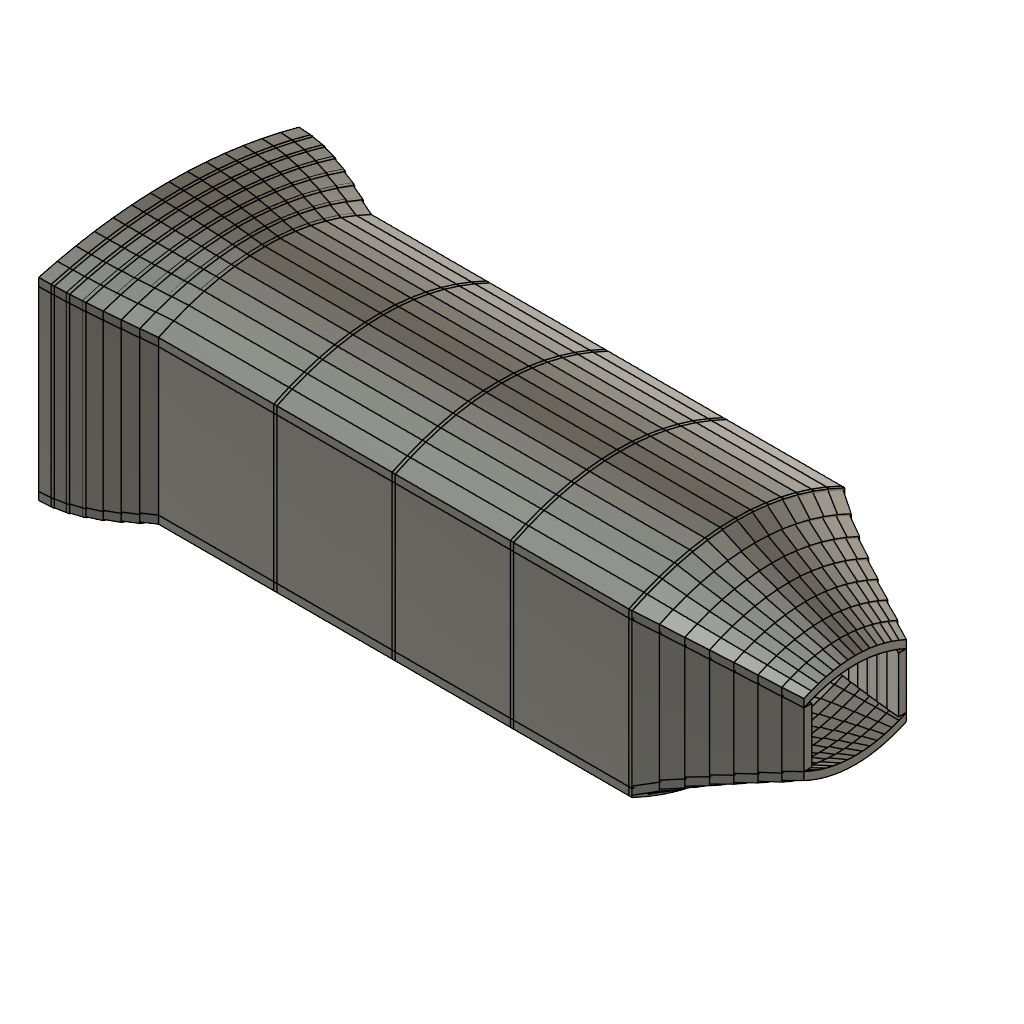
v22-casing (Autodesk Fusion 360 design; units mm, degrees)
part number: 2026-10-21-10-23-17-566
Autodesk Fusion 360 part; units mm, degrees
(part 1 of 5)
ref_plane "WorkPlane1" through (-24, 0, 0) normal (1, 0, 0) x (0, 1, 0)
sketch "roof_pa00" plane through (-24, 0, 0) normal (1, 0, 0) x (0, 0, -1)
  line L0 (-24.5, -33) -> (-25.6939, -28.2857)
  line L1 (-25.6939, -28.2857) -> (-26.7041, -23.5714)
  line L2 (-26.7041, -23.5714) -> (-27.5306, -18.8571)
  line L3 (-27.5306, -18.8571) -> (-28.1735, -14.1429)
  line L4 (-28.1735, -14.1429) -> (-28.6327, -9.4286)
  line L5 (-28.6327, -9.4286) -> (-28.9082, -4.7143)
  line L6 (-28.9082, -4.7143) -> (-29, 0)
  line L7 (-29, 0) -> (-28.9082, 4.7143)
  line L8 (-28.9082, 4.7143) -> (-28.6327, 9.4286)
  line L9 (-28.6327, 9.4286) -> (-28.1735, 14.1429)
  line L10 (-28.1735, 14.1429) -> (-27.5306, 18.8571)
  line L11 (-27.5306, 18.8571) -> (-26.7041, 23.5714)
  line L12 (-26.7041, 23.5714) -> (-25.6939, 28.2857)
  line L13 (-25.6939, 28.2857) -> (-24.5, 33)
  line L14 (-24.5, 33) -> (-22.5, 33)
  line L15 (-22.5, 33) -> (-23.6939, 28.2857)
  line L16 (-23.6939, 28.2857) -> (-24.7041, 23.5714)
  line L17 (-24.7041, 23.5714) -> (-25.5306, 18.8571)
  line L18 (-25.5306, 18.8571) -> (-26.1735, 14.1429)
  line L19 (-26.1735, 14.1429) -> (-26.6327, 9.4286)
  line L20 (-26.6327, 9.4286) -> (-26.9082, 4.7143)
  line L21 (-26.9082, 4.7143) -> (-27, 0)
  line L22 (-27, 0) -> (-26.9082, -4.7143)
  line L23 (-26.9082, -4.7143) -> (-26.6327, -9.4286)
  line L24 (-26.6327, -9.4286) -> (-26.1735, -14.1429)
  line L25 (-26.1735, -14.1429) -> (-25.5306, -18.8571)
  line L26 (-25.5306, -18.8571) -> (-24.7041, -23.5714)
  line L27 (-24.7041, -23.5714) -> (-23.6939, -28.2857)
  line L28 (-23.6939, -28.2857) -> (-22.5, -33)
  line L29 (-22.5, -33) -> (-24.5, -33)
ref_plane "WorkPlane2" through (-20.1714, 0, 0) normal (1, 0, 0) x (0, 1, 0)
sketch "roof_pb00" plane through (-20.1714, 0, 0) normal (1, 0, 0) x (0, 0, -1)
  line L0 (-24.3997, -32.8496) -> (-25.6069, -28.1568)
  line L1 (-25.6069, -28.1568) -> (-26.6284, -23.464)
  line L2 (-26.6284, -23.464) -> (-27.4641, -18.7712)
  line L3 (-27.4641, -18.7712) -> (-28.1141, -14.0784)
  line L4 (-28.1141, -14.0784) -> (-28.5784, -9.3856)
  line L5 (-28.5784, -9.3856) -> (-28.857, -4.6928)
  line L6 (-28.857, -4.6928) -> (-28.9499, 0)
  line L7 (-28.9499, 0) -> (-28.857, 4.6928)
  line L8 (-28.857, 4.6928) -> (-28.5784, 9.3856)
  line L9 (-28.5784, 9.3856) -> (-28.1141, 14.0784)
  line L10 (-28.1141, 14.0784) -> (-27.4641, 18.7712)
  line L11 (-27.4641, 18.7712) -> (-26.6284, 23.464)
  line L12 (-26.6284, 23.464) -> (-25.6069, 28.1568)
  line L13 (-25.6069, 28.1568) -> (-24.3997, 32.8496)
  line L14 (-24.3997, 32.8496) -> (-22.3997, 32.8496)
  line L15 (-22.3997, 32.8496) -> (-23.6069, 28.1568)
  line L16 (-23.6069, 28.1568) -> (-24.6284, 23.464)
  line L17 (-24.6284, 23.464) -> (-25.4641, 18.7712)
  line L18 (-25.4641, 18.7712) -> (-26.1141, 14.0784)
  line L19 (-26.1141, 14.0784) -> (-26.5784, 9.3856)
  line L20 (-26.5784, 9.3856) -> (-26.857, 4.6928)
  line L21 (-26.857, 4.6928) -> (-26.9499, 0)
  line L22 (-26.9499, 0) -> (-26.857, -4.6928)
  line L23 (-26.857, -4.6928) -> (-26.5784, -9.3856)
  line L24 (-26.5784, -9.3856) -> (-26.1141, -14.0784)
  line L25 (-26.1141, -14.0784) -> (-25.4641, -18.7712)
  line L26 (-25.4641, -18.7712) -> (-24.6284, -23.464)
  line L27 (-24.6284, -23.464) -> (-23.6069, -28.1568)
  line L28 (-23.6069, -28.1568) -> (-22.3997, -32.8496)
  line L29 (-22.3997, -32.8496) -> (-24.3997, -32.8496)
loft "Loft1" add profiles "roof_pa00", "roof_pb00" section 1 section 2 makes body 1
ref_plane "WorkPlane3" through (-20.9714, 0, 0) normal (1, 0, 0) x (0, 1, 0)
sketch "roof_pa01" plane through (-20.9714, 0, 0) normal (1, 0, 0) x (0, 0, -1)
  line L0 (-24.3997, -32.8496) -> (-25.6069, -28.1568)
  line L1 (-25.6069, -28.1568) -> (-26.6284, -23.464)
  line L2 (-26.6284, -23.464) -> (-27.4641, -18.7712)
  line L3 (-27.4641, -18.7712) -> (-28.1141, -14.0784)
  line L4 (-28.1141, -14.0784) -> (-28.5784, -9.3856)
  line L5 (-28.5784, -9.3856) -> (-28.857, -4.6928)
  line L6 (-28.857, -4.6928) -> (-28.9499, 0)
  line L7 (-28.9499, 0) -> (-28.857, 4.6928)
  line L8 (-28.857, 4.6928) -> (-28.5784, 9.3856)
  line L9 (-28.5784, 9.3856) -> (-28.1141, 14.0784)
  line L10 (-28.1141, 14.0784) -> (-27.4641, 18.7712)
  line L11 (-27.4641, 18.7712) -> (-26.6284, 23.464)
  line L12 (-26.6284, 23.464) -> (-25.6069, 28.1568)
  line L13 (-25.6069, 28.1568) -> (-24.3997, 32.8496)
  line L14 (-24.3997, 32.8496) -> (-22.3997, 32.8496)
  line L15 (-22.3997, 32.8496) -> (-23.6069, 28.1568)
  line L16 (-23.6069, 28.1568) -> (-24.6284, 23.464)
  line L17 (-24.6284, 23.464) -> (-25.4641, 18.7712)
  line L18 (-25.4641, 18.7712) -> (-26.1141, 14.0784)
  line L19 (-26.1141, 14.0784) -> (-26.5784, 9.3856)
  line L20 (-26.5784, 9.3856) -> (-26.857, 4.6928)
  line L21 (-26.857, 4.6928) -> (-26.9499, 0)
  line L22 (-26.9499, 0) -> (-26.857, -4.6928)
  line L23 (-26.857, -4.6928) -> (-26.5784, -9.3856)
  line L24 (-26.5784, -9.3856) -> (-26.1141, -14.0784)
  line L25 (-26.1141, -14.0784) -> (-25.4641, -18.7712)
  line L26 (-25.4641, -18.7712) -> (-24.6284, -23.464)
  line L27 (-24.6284, -23.464) -> (-23.6069, -28.1568)
  line L28 (-23.6069, -28.1568) -> (-22.3997, -32.8496)
  line L29 (-22.3997, -32.8496) -> (-24.3997, -32.8496)
ref_plane "WorkPlane4" through (-16.7429, 0, 0) normal (1, 0, 0) x (0, 1, 0)
sketch "roof_pb01" plane through (-16.7429, 0, 0) normal (1, 0, 0) x (0, 0, -1)
  line L0 (-24.1039, -32.4058) -> (-25.3503, -27.7764)
  line L1 (-25.3503, -27.7764) -> (-26.405, -23.147)
  line L2 (-26.405, -23.147) -> (-27.2679, -18.5176)
  line L3 (-27.2679, -18.5176) -> (-27.939, -13.8882)
  line L4 (-27.939, -13.8882) -> (-28.4184, -9.2588)
  line L5 (-28.4184, -9.2588) -> (-28.7061, -4.6294)
  line L6 (-28.7061, -4.6294) -> (-28.8019, 0)
  line L7 (-28.8019, 0) -> (-28.7061, 4.6294)
  line L8 (-28.7061, 4.6294) -> (-28.4184, 9.2588)
  line L9 (-28.4184, 9.2588) -> (-27.939, 13.8882)
  line L10 (-27.939, 13.8882) -> (-27.2679, 18.5176)
  line L11 (-27.2679, 18.5176) -> (-26.405, 23.147)
  line L12 (-26.405, 23.147) -> (-25.3503, 27.7764)
  line L13 (-25.3503, 27.7764) -> (-24.1039, 32.4058)
  line L14 (-24.1039, 32.4058) -> (-22.1039, 32.4058)
  line L15 (-22.1039, 32.4058) -> (-23.3503, 27.7764)
  line L16 (-23.3503, 27.7764) -> (-24.405, 23.147)
  line L17 (-24.405, 23.147) -> (-25.2679, 18.5176)
  line L18 (-25.2679, 18.5176) -> (-25.939, 13.8882)
  line L19 (-25.939, 13.8882) -> (-26.4184, 9.2588)
  line L20 (-26.4184, 9.2588) -> (-26.7061, 4.6294)
  line L21 (-26.7061, 4.6294) -> (-26.8019, 0)
  line L22 (-26.8019, 0) -> (-26.7061, -4.6294)
  line L23 (-26.7061, -4.6294) -> (-26.4184, -9.2588)
  line L24 (-26.4184, -9.2588) -> (-25.939, -13.8882)
  line L25 (-25.939, -13.8882) -> (-25.2679, -18.5176)
  line L26 (-25.2679, -18.5176) -> (-24.405, -23.147)
  line L27 (-24.405, -23.147) -> (-23.3503, -27.7764)
  line L28 (-23.3503, -27.7764) -> (-22.1039, -32.4058)
  line L29 (-22.1039, -32.4058) -> (-24.1039, -32.4058)
loft "Loft2" add profiles "roof_pa01", "roof_pb01" section 1 section 2 separate body makes body 2
ref_plane "WorkPlane5" through (-17.5429, 0, 0) normal (1, 0, 0) x (0, 1, 0)
sketch "roof_pa02" plane through (-17.5429, 0, 0) normal (1, 0, 0) x (0, 0, -1)
  line L0 (-24.1039, -32.4058) -> (-25.3503, -27.7764)
  line L1 (-25.3503, -27.7764) -> (-26.405, -23.147)
  line L2 (-26.405, -23.147) -> (-27.2679, -18.5176)
  line L3 (-27.2679, -18.5176) -> (-27.939, -13.8882)
  line L4 (-27.939, -13.8882) -> (-28.4184, -9.2588)
  line L5 (-28.4184, -9.2588) -> (-28.7061, -4.6294)
  line L6 (-28.7061, -4.6294) -> (-28.8019, 0)
  line L7 (-28.8019, 0) -> (-28.7061, 4.6294)
  line L8 (-28.7061, 4.6294) -> (-28.4184, 9.2588)
  line L9 (-28.4184, 9.2588) -> (-27.939, 13.8882)
  line L10 (-27.939, 13.8882) -> (-27.2679, 18.5176)
  line L11 (-27.2679, 18.5176) -> (-26.405, 23.147)
  line L12 (-26.405, 23.147) -> (-25.3503, 27.7764)
  line L13 (-25.3503, 27.7764) -> (-24.1039, 32.4058)
  line L14 (-24.1039, 32.4058) -> (-22.1039, 32.4058)
  line L15 (-22.1039, 32.4058) -> (-23.3503, 27.7764)
  line L16 (-23.3503, 27.7764) -> (-24.405, 23.147)
  line L17 (-24.405, 23.147) -> (-25.2679, 18.5176)
  line L18 (-25.2679, 18.5176) -> (-25.939, 13.8882)
  line L19 (-25.939, 13.8882) -> (-26.4184, 9.2588)
  line L20 (-26.4184, 9.2588) -> (-26.7061, 4.6294)
  line L21 (-26.7061, 4.6294) -> (-26.8019, 0)
  line L22 (-26.8019, 0) -> (-26.7061, -4.6294)
  line L23 (-26.7061, -4.6294) -> (-26.4184, -9.2588)
  line L24 (-26.4184, -9.2588) -> (-25.939, -13.8882)
  line L25 (-25.939, -13.8882) -> (-25.2679, -18.5176)
  line L26 (-25.2679, -18.5176) -> (-24.405, -23.147)
  line L27 (-24.405, -23.147) -> (-23.3503, -27.7764)
  line L28 (-23.3503, -27.7764) -> (-22.1039, -32.4058)
  line L29 (-22.1039, -32.4058) -> (-24.1039, -32.4058)
ref_plane "WorkPlane6" through (-13.3143, 0, 0) normal (1, 0, 0) x (0, 1, 0)
sketch "roof_pb02" plane through (-13.3143, 0, 0) normal (1, 0, 0) x (0, 0, -1)
  line L0 (-23.6273, -31.691) -> (-24.937, -27.1637)
  line L1 (-24.937, -27.1637) -> (-26.0451, -22.6364)
  line L2 (-26.0451, -22.6364) -> (-26.9518, -18.1091)
  line L3 (-26.9518, -18.1091) -> (-27.657, -13.5819)
  line L4 (-27.657, -13.5819) -> (-28.1607, -9.0546)
  line L5 (-28.1607, -9.0546) -> (-28.4629, -4.5273)
  line L6 (-28.4629, -4.5273) -> (-28.5637, 0)
  line L7 (-28.5637, 0) -> (-28.4629, 4.5273)
  line L8 (-28.4629, 4.5273) -> (-28.1607, 9.0546)
  line L9 (-28.1607, 9.0546) -> (-27.657, 13.5819)
  line L10 (-27.657, 13.5819) -> (-26.9518, 18.1091)
  line L11 (-26.9518, 18.1091) -> (-26.0451, 22.6364)
  line L12 (-26.0451, 22.6364) -> (-24.937, 27.1637)
  line L13 (-24.937, 27.1637) -> (-23.6273, 31.691)
  line L14 (-23.6273, 31.691) -> (-21.6273, 31.691)
  line L15 (-21.6273, 31.691) -> (-22.937, 27.1637)
  line L16 (-22.937, 27.1637) -> (-24.0451, 22.6364)
  line L17 (-24.0451, 22.6364) -> (-24.9518, 18.1091)
  line L18 (-24.9518, 18.1091) -> (-25.657, 13.5819)
  line L19 (-25.657, 13.5819) -> (-26.1607, 9.0546)
  line L20 (-26.1607, 9.0546) -> (-26.4629, 4.5273)
  line L21 (-26.4629, 4.5273) -> (-26.5637, 0)
  line L22 (-26.5637, 0) -> (-26.4629, -4.5273)
  line L23 (-26.4629, -4.5273) -> (-26.1607, -9.0546)
  line L24 (-26.1607, -9.0546) -> (-25.657, -13.5819)
  line L25 (-25.657, -13.5819) -> (-24.9518, -18.1091)
  line L26 (-24.9518, -18.1091) -> (-24.0451, -22.6364)
  line L27 (-24.0451, -22.6364) -> (-22.937, -27.1637)
  line L28 (-22.937, -27.1637) -> (-21.6273, -31.691)
  line L29 (-21.6273, -31.691) -> (-23.6273, -31.691)
loft "Loft3" add profiles "roof_pa02", "roof_pb02" section 1 section 2 separate body makes body 3
ref_plane "WorkPlane7" through (-14.1143, 0, 0) normal (1, 0, 0) x (0, 1, 0)
sketch "roof_pa03" plane through (-14.1143, 0, 0) normal (1, 0, 0) x (0, 0, -1)
  line L0 (-23.6273, -31.691) -> (-24.937, -27.1637)
  line L1 (-24.937, -27.1637) -> (-26.0451, -22.6364)
  line L2 (-26.0451, -22.6364) -> (-26.9518, -18.1091)
  line L3 (-26.9518, -18.1091) -> (-27.657, -13.5819)
  line L4 (-27.657, -13.5819) -> (-28.1607, -9.0546)
  line L5 (-28.1607, -9.0546) -> (-28.4629, -4.5273)
  line L6 (-28.4629, -4.5273) -> (-28.5637, 0)
  line L7 (-28.5637, 0) -> (-28.4629, 4.5273)
  line L8 (-28.4629, 4.5273) -> (-28.1607, 9.0546)
  line L9 (-28.1607, 9.0546) -> (-27.657, 13.5819)
  line L10 (-27.657, 13.5819) -> (-26.9518, 18.1091)
  line L11 (-26.9518, 18.1091) -> (-26.0451, 22.6364)
  line L12 (-26.0451, 22.6364) -> (-24.937, 27.1637)
  line L13 (-24.937, 27.1637) -> (-23.6273, 31.691)
  line L14 (-23.6273, 31.691) -> (-21.6273, 31.691)
  line L15 (-21.6273, 31.691) -> (-22.937, 27.1637)
  line L16 (-22.937, 27.1637) -> (-24.0451, 22.6364)
  line L17 (-24.0451, 22.6364) -> (-24.9518, 18.1091)
  line L18 (-24.9518, 18.1091) -> (-25.657, 13.5819)
  line L19 (-25.657, 13.5819) -> (-26.1607, 9.0546)
  line L20 (-26.1607, 9.0546) -> (-26.4629, 4.5273)
  line L21 (-26.4629, 4.5273) -> (-26.5637, 0)
  line L22 (-26.5637, 0) -> (-26.4629, -4.5273)
  line L23 (-26.4629, -4.5273) -> (-26.1607, -9.0546)
  line L24 (-26.1607, -9.0546) -> (-25.657, -13.5819)
  line L25 (-25.657, -13.5819) -> (-24.9518, -18.1091)
  line L26 (-24.9518, -18.1091) -> (-24.0451, -22.6364)
  line L27 (-24.0451, -22.6364) -> (-22.937, -27.1637)
  line L28 (-22.937, -27.1637) -> (-21.6273, -31.691)
  line L29 (-21.6273, -31.691) -> (-23.6273, -31.691)
ref_plane "WorkPlane8" through (-9.8857, 0, 0) normal (1, 0, 0) x (0, 1, 0)
sketch "roof_pb03" plane through (-9.8857, 0, 0) normal (1, 0, 0) x (0, 0, -1)
  line L0 (-22.994, -30.7409) -> (-24.3876, -26.3494)
  line L1 (-24.3876, -26.3494) -> (-25.5669, -21.9578)
  line L2 (-25.5669, -21.9578) -> (-26.5317, -17.5663)
  line L3 (-26.5317, -17.5663) -> (-27.2821, -13.1747)
  line L4 (-27.2821, -13.1747) -> (-27.8182, -8.7831)
  line L5 (-27.8182, -8.7831) -> (-28.1398, -4.3916)
  line L6 (-28.1398, -4.3916) -> (-28.247, 0)
  line L7 (-28.247, 0) -> (-28.1398, 4.3916)
  line L8 (-28.1398, 4.3916) -> (-27.8182, 8.7831)
  line L9 (-27.8182, 8.7831) -> (-27.2821, 13.1747)
  line L10 (-27.2821, 13.1747) -> (-26.5317, 17.5663)
  line L11 (-26.5317, 17.5663) -> (-25.5669, 21.9578)
  line L12 (-25.5669, 21.9578) -> (-24.3876, 26.3494)
  line L13 (-24.3876, 26.3494) -> (-22.994, 30.7409)
  line L14 (-22.994, 30.7409) -> (-20.994, 30.7409)
  line L15 (-20.994, 30.7409) -> (-22.3876, 26.3494)
  line L16 (-22.3876, 26.3494) -> (-23.5669, 21.9578)
  line L17 (-23.5669, 21.9578) -> (-24.5317, 17.5663)
  line L18 (-24.5317, 17.5663) -> (-25.2821, 13.1747)
  line L19 (-25.2821, 13.1747) -> (-25.8182, 8.7831)
  line L20 (-25.8182, 8.7831) -> (-26.1398, 4.3916)
  line L21 (-26.1398, 4.3916) -> (-26.247, 0)
  line L22 (-26.247, 0) -> (-26.1398, -4.3916)
  line L23 (-26.1398, -4.3916) -> (-25.8182, -8.7831)
  line L24 (-25.8182, -8.7831) -> (-25.2821, -13.1747)
  line L25 (-25.2821, -13.1747) -> (-24.5317, -17.5663)
  line L26 (-24.5317, -17.5663) -> (-23.5669, -21.9578)
  line L27 (-23.5669, -21.9578) -> (-22.3876, -26.3494)
  line L28 (-22.3876, -26.3494) -> (-20.994, -30.7409)
  line L29 (-20.994, -30.7409) -> (-22.994, -30.7409)
loft "Loft4" add profiles "roof_pa03", "roof_pb03" section 1 section 2 separate body makes body 4
ref_plane "WorkPlane9" through (-10.6857, 0, 0) normal (1, 0, 0) x (0, 1, 0)
sketch "roof_pa04" plane through (-10.6857, 0, 0) normal (1, 0, 0) x (0, 0, -1)
  line L0 (-22.994, -30.7409) -> (-24.3876, -26.3494)
  line L1 (-24.3876, -26.3494) -> (-25.5669, -21.9578)
  line L2 (-25.5669, -21.9578) -> (-26.5317, -17.5663)
  line L3 (-26.5317, -17.5663) -> (-27.2821, -13.1747)
  line L4 (-27.2821, -13.1747) -> (-27.8182, -8.7831)
  line L5 (-27.8182, -8.7831) -> (-28.1398, -4.3916)
  line L6 (-28.1398, -4.3916) -> (-28.247, 0)
  line L7 (-28.247, 0) -> (-28.1398, 4.3916)
  line L8 (-28.1398, 4.3916) -> (-27.8182, 8.7831)
  line L9 (-27.8182, 8.7831) -> (-27.2821, 13.1747)
  line L10 (-27.2821, 13.1747) -> (-26.5317, 17.5663)
  line L11 (-26.5317, 17.5663) -> (-25.5669, 21.9578)
  line L12 (-25.5669, 21.9578) -> (-24.3876, 26.3494)
  line L13 (-24.3876, 26.3494) -> (-22.994, 30.7409)
  line L14 (-22.994, 30.7409) -> (-20.994, 30.7409)
  line L15 (-20.994, 30.7409) -> (-22.3876, 26.3494)
  line L16 (-22.3876, 26.3494) -> (-23.5669, 21.9578)
  line L17 (-23.5669, 21.9578) -> (-24.5317, 17.5663)
  line L18 (-24.5317, 17.5663) -> (-25.2821, 13.1747)
  line L19 (-25.2821, 13.1747) -> (-25.8182, 8.7831)
  line L20 (-25.8182, 8.7831) -> (-26.1398, 4.3916)
  line L21 (-26.1398, 4.3916) -> (-26.247, 0)
  line L22 (-26.247, 0) -> (-26.1398, -4.3916)
  line L23 (-26.1398, -4.3916) -> (-25.8182, -8.7831)
  line L24 (-25.8182, -8.7831) -> (-25.2821, -13.1747)
  line L25 (-25.2821, -13.1747) -> (-24.5317, -17.5663)
  line L26 (-24.5317, -17.5663) -> (-23.5669, -21.9578)
  line L27 (-23.5669, -21.9578) -> (-22.3876, -26.3494)
  line L28 (-22.3876, -26.3494) -> (-20.994, -30.7409)
  line L29 (-20.994, -30.7409) -> (-22.994, -30.7409)
ref_plane "WorkPlane10" through (-6.4571, 0, 0) normal (1, 0, 0) x (0, 1, 0)
sketch "roof_pb04" plane through (-6.4571, 0, 0) normal (1, 0, 0) x (0, 0, -1)
  line L0 (-22.2355, -29.6033) -> (-23.7298, -25.3743)
  line L1 (-23.7298, -25.3743) -> (-24.9942, -21.1452)
  line L2 (-24.9942, -21.1452) -> (-26.0287, -16.9162)
  line L3 (-26.0287, -16.9162) -> (-26.8333, -12.6871)
  line L4 (-26.8333, -12.6871) -> (-27.408, -8.4581)
  line L5 (-27.408, -8.4581) -> (-27.7528, -4.229)
  line L6 (-27.7528, -4.229) -> (-27.8678, 0)
  line L7 (-27.8678, 0) -> (-27.7528, 4.229)
  line L8 (-27.7528, 4.229) -> (-27.408, 8.4581)
  line L9 (-27.408, 8.4581) -> (-26.8333, 12.6871)
  line L10 (-26.8333, 12.6871) -> (-26.0287, 16.9162)
  line L11 (-26.0287, 16.9162) -> (-24.9942, 21.1452)
  line L12 (-24.9942, 21.1452) -> (-23.7298, 25.3743)
  line L13 (-23.7298, 25.3743) -> (-22.2355, 29.6033)
  line L14 (-22.2355, 29.6033) -> (-20.2355, 29.6033)
  line L15 (-20.2355, 29.6033) -> (-21.7298, 25.3743)
  line L16 (-21.7298, 25.3743) -> (-22.9942, 21.1452)
  line L17 (-22.9942, 21.1452) -> (-24.0287, 16.9162)
  line L18 (-24.0287, 16.9162) -> (-24.8333, 12.6871)
  line L19 (-24.8333, 12.6871) -> (-25.408, 8.4581)
  line L20 (-25.408, 8.4581) -> (-25.7528, 4.229)
  line L21 (-25.7528, 4.229) -> (-25.8678, 0)
  line L22 (-25.8678, 0) -> (-25.7528, -4.229)
  line L23 (-25.7528, -4.229) -> (-25.408, -8.4581)
  line L24 (-25.408, -8.4581) -> (-24.8333, -12.6871)
  line L25 (-24.8333, -12.6871) -> (-24.0287, -16.9162)
  line L26 (-24.0287, -16.9162) -> (-22.9942, -21.1452)
  line L27 (-22.9942, -21.1452) -> (-21.7298, -25.3743)
  line L28 (-21.7298, -25.3743) -> (-20.2355, -29.6033)
  line L29 (-20.2355, -29.6033) -> (-22.2355, -29.6033)
loft "Loft5" add profiles "roof_pa04", "roof_pb04" section 1 section 2 separate body makes body 5
ref_plane "WorkPlane11" through (-7.2571, 0, 0) normal (1, 0, 0) x (0, 1, 0)
sketch "roof_pa05" plane through (-7.2571, 0, 0) normal (1, 0, 0) x (0, 0, -1)
  line L0 (-22.2355, -29.6033) -> (-23.7298, -25.3743)
  line L1 (-23.7298, -25.3743) -> (-24.9942, -21.1452)
  line L2 (-24.9942, -21.1452) -> (-26.0287, -16.9162)
  line L3 (-26.0287, -16.9162) -> (-26.8333, -12.6871)
  line L4 (-26.8333, -12.6871) -> (-27.408, -8.4581)
  line L5 (-27.408, -8.4581) -> (-27.7528, -4.229)
  line L6 (-27.7528, -4.229) -> (-27.8678, 0)
  line L7 (-27.8678, 0) -> (-27.7528, 4.229)
  line L8 (-27.7528, 4.229) -> (-27.408, 8.4581)
  line L9 (-27.408, 8.4581) -> (-26.8333, 12.6871)
  line L10 (-26.8333, 12.6871) -> (-26.0287, 16.9162)
  line L11 (-26.0287, 16.9162) -> (-24.9942, 21.1452)
  line L12 (-24.9942, 21.1452) -> (-23.7298, 25.3743)
  line L13 (-23.7298, 25.3743) -> (-22.2355, 29.6033)
  line L14 (-22.2355, 29.6033) -> (-20.2355, 29.6033)
  line L15 (-20.2355, 29.6033) -> (-21.7298, 25.3743)
  line L16 (-21.7298, 25.3743) -> (-22.9942, 21.1452)
  line L17 (-22.9942, 21.1452) -> (-24.0287, 16.9162)
  line L18 (-24.0287, 16.9162) -> (-24.8333, 12.6871)
  line L19 (-24.8333, 12.6871) -> (-25.408, 8.4581)
  line L20 (-25.408, 8.4581) -> (-25.7528, 4.229)
  line L21 (-25.7528, 4.229) -> (-25.8678, 0)
  line L22 (-25.8678, 0) -> (-25.7528, -4.229)
  line L23 (-25.7528, -4.229) -> (-25.408, -8.4581)
  line L24 (-25.408, -8.4581) -> (-24.8333, -12.6871)
  line L25 (-24.8333, -12.6871) -> (-24.0287, -16.9162)
  line L26 (-24.0287, -16.9162) -> (-22.9942, -21.1452)
  line L27 (-22.9942, -21.1452) -> (-21.7298, -25.3743)
  line L28 (-21.7298, -25.3743) -> (-20.2355, -29.6033)
  line L29 (-20.2355, -29.6033) -> (-22.2355, -29.6033)
ref_plane "WorkPlane12" through (-3.0286, 0, 0) normal (1, 0, 0) x (0, 1, 0)
sketch "roof_pb05" plane through (-3.0286, 0, 0) normal (1, 0, 0) x (0, 0, -1)
  line L0 (-21.3901, -28.3351) -> (-22.9965, -24.2873)
  line L1 (-22.9965, -24.2873) -> (-24.3558, -20.2394)
  line L2 (-24.3558, -20.2394) -> (-25.4679, -16.1915)
  line L3 (-25.4679, -16.1915) -> (-26.3329, -12.1436)
  line L4 (-26.3329, -12.1436) -> (-26.9508, -8.0958)
  line L5 (-26.9508, -8.0958) -> (-27.3215, -4.0479)
  line L6 (-27.3215, -4.0479) -> (-27.445, 0)
  line L7 (-27.445, 0) -> (-27.3215, 4.0479)
  line L8 (-27.3215, 4.0479) -> (-26.9508, 8.0958)
  line L9 (-26.9508, 8.0958) -> (-26.3329, 12.1436)
  line L10 (-26.3329, 12.1436) -> (-25.4679, 16.1915)
  line L11 (-25.4679, 16.1915) -> (-24.3558, 20.2394)
  line L12 (-24.3558, 20.2394) -> (-22.9965, 24.2873)
  line L13 (-22.9965, 24.2873) -> (-21.3901, 28.3351)
  line L14 (-21.3901, 28.3351) -> (-19.3901, 28.3351)
  line L15 (-19.3901, 28.3351) -> (-20.9965, 24.2873)
  line L16 (-20.9965, 24.2873) -> (-22.3558, 20.2394)
  line L17 (-22.3558, 20.2394) -> (-23.4679, 16.1915)
  line L18 (-23.4679, 16.1915) -> (-24.3329, 12.1436)
  line L19 (-24.3329, 12.1436) -> (-24.9508, 8.0958)
  line L20 (-24.9508, 8.0958) -> (-25.3215, 4.0479)
  line L21 (-25.3215, 4.0479) -> (-25.445, 0)
  line L22 (-25.445, 0) -> (-25.3215, -4.0479)
  line L23 (-25.3215, -4.0479) -> (-24.9508, -8.0958)
  line L24 (-24.9508, -8.0958) -> (-24.3329, -12.1436)
  line L25 (-24.3329, -12.1436) -> (-23.4679, -16.1915)
  line L26 (-23.4679, -16.1915) -> (-22.3558, -20.2394)
  line L27 (-22.3558, -20.2394) -> (-20.9965, -24.2873)
  line L28 (-20.9965, -24.2873) -> (-19.3901, -28.3351)
  line L29 (-19.3901, -28.3351) -> (-21.3901, -28.3351)
loft "Loft6" add profiles "roof_pa05", "roof_pb05" section 1 section 2 separate body makes body 6
ref_plane "WorkPlane13" through (-3.8286, 0, 0) normal (1, 0, 0) x (0, 1, 0)
sketch "roof_pa06" plane through (-3.8286, 0, 0) normal (1, 0, 0) x (0, 0, -1)
  line L0 (-21.3901, -28.3351) -> (-22.9965, -24.2873)
  line L1 (-22.9965, -24.2873) -> (-24.3558, -20.2394)
  line L2 (-24.3558, -20.2394) -> (-25.4679, -16.1915)
  line L3 (-25.4679, -16.1915) -> (-26.3329, -12.1436)
  line L4 (-26.3329, -12.1436) -> (-26.9508, -8.0958)
  line L5 (-26.9508, -8.0958) -> (-27.3215, -4.0479)
  line L6 (-27.3215, -4.0479) -> (-27.445, 0)
  line L7 (-27.445, 0) -> (-27.3215, 4.0479)
  line L8 (-27.3215, 4.0479) -> (-26.9508, 8.0958)
  line L9 (-26.9508, 8.0958) -> (-26.3329, 12.1436)
  line L10 (-26.3329, 12.1436) -> (-25.4679, 16.1915)
  line L11 (-25.4679, 16.1915) -> (-24.3558, 20.2394)
  line L12 (-24.3558, 20.2394) -> (-22.9965, 24.2873)
  line L13 (-22.9965, 24.2873) -> (-21.3901, 28.3351)
  line L14 (-21.3901, 28.3351) -> (-19.3901, 28.3351)
  line L15 (-19.3901, 28.3351) -> (-20.9965, 24.2873)
  line L16 (-20.9965, 24.2873) -> (-22.3558, 20.2394)
  line L17 (-22.3558, 20.2394) -> (-23.4679, 16.1915)
  line L18 (-23.4679, 16.1915) -> (-24.3329, 12.1436)
  line L19 (-24.3329, 12.1436) -> (-24.9508, 8.0958)
  line L20 (-24.9508, 8.0958) -> (-25.3215, 4.0479)
  line L21 (-25.3215, 4.0479) -> (-25.445, 0)
  line L22 (-25.445, 0) -> (-25.3215, -4.0479)
  line L23 (-25.3215, -4.0479) -> (-24.9508, -8.0958)
  line L24 (-24.9508, -8.0958) -> (-24.3329, -12.1436)
  line L25 (-24.3329, -12.1436) -> (-23.4679, -16.1915)
  line L26 (-23.4679, -16.1915) -> (-22.3558, -20.2394)
  line L27 (-22.3558, -20.2394) -> (-20.9965, -24.2873)
  line L28 (-20.9965, -24.2873) -> (-19.3901, -28.3351)
  line L29 (-19.3901, -28.3351) -> (-21.3901, -28.3351)
ref_plane "WorkPlane14" through (0.4, 0, 0) normal (1, 0, 0) x (0, 1, 0)
sketch "roof_pb06" plane through (0.4, 0, 0) normal (1, 0, 0) x (0, 0, -1)
  line L0 (-20.5, -27) -> (-22.2245, -23.1429)
  line L1 (-22.2245, -23.1429) -> (-23.6837, -19.2857)
  line L2 (-23.6837, -19.2857) -> (-24.8776, -15.4286)
  line L3 (-24.8776, -15.4286) -> (-25.8061, -11.5714)
  line L4 (-25.8061, -11.5714) -> (-26.4694, -7.7143)
  line L5 (-26.4694, -7.7143) -> (-26.8673, -3.8571)
  line L6 (-26.8673, -3.8571) -> (-27, 0)
  line L7 (-27, 0) -> (-26.8673, 3.8571)
  line L8 (-26.8673, 3.8571) -> (-26.4694, 7.7143)
  line L9 (-26.4694, 7.7143) -> (-25.8061, 11.5714)
  line L10 (-25.8061, 11.5714) -> (-24.8776, 15.4286)
  line L11 (-24.8776, 15.4286) -> (-23.6837, 19.2857)
  line L12 (-23.6837, 19.2857) -> (-22.2245, 23.1429)
  line L13 (-22.2245, 23.1429) -> (-20.5, 27)
  line L14 (-20.5, 27) -> (-18.5, 27)
  line L15 (-18.5, 27) -> (-20.2245, 23.1429)
  line L16 (-20.2245, 23.1429) -> (-21.6837, 19.2857)
  line L17 (-21.6837, 19.2857) -> (-22.8776, 15.4286)
  line L18 (-22.8776, 15.4286) -> (-23.8061, 11.5714)
  line L19 (-23.8061, 11.5714) -> (-24.4694, 7.7143)
  line L20 (-24.4694, 7.7143) -> (-24.8673, 3.8571)
  line L21 (-24.8673, 3.8571) -> (-25, 0)
  line L22 (-25, 0) -> (-24.8673, -3.8571)
  line L23 (-24.8673, -3.8571) -> (-24.4694, -7.7143)
  line L24 (-24.4694, -7.7143) -> (-23.8061, -11.5714)
  line L25 (-23.8061, -11.5714) -> (-22.8776, -15.4286)
  line L26 (-22.8776, -15.4286) -> (-21.6837, -19.2857)
  line L27 (-21.6837, -19.2857) -> (-20.2245, -23.1429)
  line L28 (-20.2245, -23.1429) -> (-18.5, -27)
  line L29 (-18.5, -27) -> (-20.5, -27)
loft "Loft7" add profiles "roof_pa06", "roof_pb06" section 1 section 2 separate body makes body 7
ref_plane "WorkPlane15" through (-0.4, 0, 0) normal (1, 0, 0) x (0, 1, 0)
sketch "roof_pa07" plane through (-0.4, 0, 0) normal (1, 0, 0) x (0, 0, -1)
  line L0 (-20.5, -27) -> (-22.2245, -23.1429)
  line L1 (-22.2245, -23.1429) -> (-23.6837, -19.2857)
  line L2 (-23.6837, -19.2857) -> (-24.8776, -15.4286)
  line L3 (-24.8776, -15.4286) -> (-25.8061, -11.5714)
  line L4 (-25.8061, -11.5714) -> (-26.4694, -7.7143)
  line L5 (-26.4694, -7.7143) -> (-26.8673, -3.8571)
  line L6 (-26.8673, -3.8571) -> (-27, 0)
  line L7 (-27, 0) -> (-26.8673, 3.8571)
  line L8 (-26.8673, 3.8571) -> (-26.4694, 7.7143)
  line L9 (-26.4694, 7.7143) -> (-25.8061, 11.5714)
  line L10 (-25.8061, 11.5714) -> (-24.8776, 15.4286)
  line L11 (-24.8776, 15.4286) -> (-23.6837, 19.2857)
  line L12 (-23.6837, 19.2857) -> (-22.2245, 23.1429)
  line L13 (-22.2245, 23.1429) -> (-20.5, 27)
  line L14 (-20.5, 27) -> (-18.5, 27)
  line L15 (-18.5, 27) -> (-20.2245, 23.1429)
  line L16 (-20.2245, 23.1429) -> (-21.6837, 19.2857)
  line L17 (-21.6837, 19.2857) -> (-22.8776, 15.4286)
  line L18 (-22.8776, 15.4286) -> (-23.8061, 11.5714)
  line L19 (-23.8061, 11.5714) -> (-24.4694, 7.7143)
  line L20 (-24.4694, 7.7143) -> (-24.8673, 3.8571)
  line L21 (-24.8673, 3.8571) -> (-25, 0)
  line L22 (-25, 0) -> (-24.8673, -3.8571)
  line L23 (-24.8673, -3.8571) -> (-24.4694, -7.7143)
  line L24 (-24.4694, -7.7143) -> (-23.8061, -11.5714)
  line L25 (-23.8061, -11.5714) -> (-22.8776, -15.4286)
  line L26 (-22.8776, -15.4286) -> (-21.6837, -19.2857)
  line L27 (-21.6837, -19.2857) -> (-20.2245, -23.1429)
  line L28 (-20.2245, -23.1429) -> (-18.5, -27)
  line L29 (-18.5, -27) -> (-20.5, -27)
ref_plane "WorkPlane16" through (30.4, 0, 0) normal (1, 0, 0) x (0, 1, 0)
sketch "roof_pb07" plane through (30.4, 0, 0) normal (1, 0, 0) x (0, 0, -1)
  line L0 (-20.5, -27) -> (-22.2245, -23.1429)
  line L1 (-22.2245, -23.1429) -> (-23.6837, -19.2857)
  line L2 (-23.6837, -19.2857) -> (-24.8776, -15.4286)
  line L3 (-24.8776, -15.4286) -> (-25.8061, -11.5714)
  line L4 (-25.8061, -11.5714) -> (-26.4694, -7.7143)
  line L5 (-26.4694, -7.7143) -> (-26.8673, -3.8571)
  line L6 (-26.8673, -3.8571) -> (-27, 0)
  line L7 (-27, 0) -> (-26.8673, 3.8571)
  line L8 (-26.8673, 3.8571) -> (-26.4694, 7.7143)
  line L9 (-26.4694, 7.7143) -> (-25.8061, 11.5714)
  line L10 (-25.8061, 11.5714) -> (-24.8776, 15.4286)
  line L11 (-24.8776, 15.4286) -> (-23.6837, 19.2857)
  line L12 (-23.6837, 19.2857) -> (-22.2245, 23.1429)
  line L13 (-22.2245, 23.1429) -> (-20.5, 27)
  line L14 (-20.5, 27) -> (-18.5, 27)
  line L15 (-18.5, 27) -> (-20.2245, 23.1429)
  line L16 (-20.2245, 23.1429) -> (-21.6837, 19.2857)
  line L17 (-21.6837, 19.2857) -> (-22.8776, 15.4286)
  line L18 (-22.8776, 15.4286) -> (-23.8061, 11.5714)
  line L19 (-23.8061, 11.5714) -> (-24.4694, 7.7143)
  line L20 (-24.4694, 7.7143) -> (-24.8673, 3.8571)
  line L21 (-24.8673, 3.8571) -> (-25, 0)
  line L22 (-25, 0) -> (-24.8673, -3.8571)
  line L23 (-24.8673, -3.8571) -> (-24.4694, -7.7143)
  line L24 (-24.4694, -7.7143) -> (-23.8061, -11.5714)
  line L25 (-23.8061, -11.5714) -> (-22.8776, -15.4286)
  line L26 (-22.8776, -15.4286) -> (-21.6837, -19.2857)
  line L27 (-21.6837, -19.2857) -> (-20.2245, -23.1429)
  line L28 (-20.2245, -23.1429) -> (-18.5, -27)
  line L29 (-18.5, -27) -> (-20.5, -27)
loft "Loft8" add profiles "roof_pa07", "roof_pb07" section 1 section 2 separate body makes body 8
ref_plane "WorkPlane17" through (29.6, 0, 0) normal (1, 0, 0) x (0, 1, 0)
sketch "roof_pa08" plane through (29.6, 0, 0) normal (1, 0, 0) x (0, 0, -1)
  line L0 (-20.5, -27) -> (-22.2245, -23.1429)
  line L1 (-22.2245, -23.1429) -> (-23.6837, -19.2857)
  line L2 (-23.6837, -19.2857) -> (-24.8776, -15.4286)
  line L3 (-24.8776, -15.4286) -> (-25.8061, -11.5714)
  line L4 (-25.8061, -11.5714) -> (-26.4694, -7.7143)
  line L5 (-26.4694, -7.7143) -> (-26.8673, -3.8571)
  line L6 (-26.8673, -3.8571) -> (-27, 0)
  line L7 (-27, 0) -> (-26.8673, 3.8571)
  line L8 (-26.8673, 3.8571) -> (-26.4694, 7.7143)
  line L9 (-26.4694, 7.7143) -> (-25.8061, 11.5714)
  line L10 (-25.8061, 11.5714) -> (-24.8776, 15.4286)
  line L11 (-24.8776, 15.4286) -> (-23.6837, 19.2857)
  line L12 (-23.6837, 19.2857) -> (-22.2245, 23.1429)
  line L13 (-22.2245, 23.1429) -> (-20.5, 27)
  line L14 (-20.5, 27) -> (-18.5, 27)
  line L15 (-18.5, 27) -> (-20.2245, 23.1429)
  line L16 (-20.2245, 23.1429) -> (-21.6837, 19.2857)
  line L17 (-21.6837, 19.2857) -> (-22.8776, 15.4286)
  line L18 (-22.8776, 15.4286) -> (-23.8061, 11.5714)
  line L19 (-23.8061, 11.5714) -> (-24.4694, 7.7143)
  line L20 (-24.4694, 7.7143) -> (-24.8673, 3.8571)
  line L21 (-24.8673, 3.8571) -> (-25, 0)
  line L22 (-25, 0) -> (-24.8673, -3.8571)
  line L23 (-24.8673, -3.8571) -> (-24.4694, -7.7143)
  line L24 (-24.4694, -7.7143) -> (-23.8061, -11.5714)
  line L25 (-23.8061, -11.5714) -> (-22.8776, -15.4286)
  line L26 (-22.8776, -15.4286) -> (-21.6837, -19.2857)
  line L27 (-21.6837, -19.2857) -> (-20.2245, -23.1429)
  line L28 (-20.2245, -23.1429) -> (-18.5, -27)
  line L29 (-18.5, -27) -> (-20.5, -27)
ref_plane "WorkPlane18" through (60.4, 0, 0) normal (1, 0, 0) x (0, 1, 0)
sketch "roof_pb08" plane through (60.4, 0, 0) normal (1, 0, 0) x (0, 0, -1)
  line L0 (-20.5, -27) -> (-22.2245, -23.1429)
  line L1 (-22.2245, -23.1429) -> (-23.6837, -19.2857)
  line L2 (-23.6837, -19.2857) -> (-24.8776, -15.4286)
  line L3 (-24.8776, -15.4286) -> (-25.8061, -11.5714)
  line L4 (-25.8061, -11.5714) -> (-26.4694, -7.7143)
  line L5 (-26.4694, -7.7143) -> (-26.8673, -3.8571)
  line L6 (-26.8673, -3.8571) -> (-27, 0)
  line L7 (-27, 0) -> (-26.8673, 3.8571)
  line L8 (-26.8673, 3.8571) -> (-26.4694, 7.7143)
  line L9 (-26.4694, 7.7143) -> (-25.8061, 11.5714)
  line L10 (-25.8061, 11.5714) -> (-24.8776, 15.4286)
  line L11 (-24.8776, 15.4286) -> (-23.6837, 19.2857)
  line L12 (-23.6837, 19.2857) -> (-22.2245, 23.1429)
  line L13 (-22.2245, 23.1429) -> (-20.5, 27)
  line L14 (-20.5, 27) -> (-18.5, 27)
  line L15 (-18.5, 27) -> (-20.2245, 23.1429)
  line L16 (-20.2245, 23.1429) -> (-21.6837, 19.2857)
  line L17 (-21.6837, 19.2857) -> (-22.8776, 15.4286)
  line L18 (-22.8776, 15.4286) -> (-23.8061, 11.5714)
  line L19 (-23.8061, 11.5714) -> (-24.4694, 7.7143)
  line L20 (-24.4694, 7.7143) -> (-24.8673, 3.8571)
  line L21 (-24.8673, 3.8571) -> (-25, 0)
  line L22 (-25, 0) -> (-24.8673, -3.8571)
  line L23 (-24.8673, -3.8571) -> (-24.4694, -7.7143)
  line L24 (-24.4694, -7.7143) -> (-23.8061, -11.5714)
  line L25 (-23.8061, -11.5714) -> (-22.8776, -15.4286)
  line L26 (-22.8776, -15.4286) -> (-21.6837, -19.2857)
  line L27 (-21.6837, -19.2857) -> (-20.2245, -23.1429)
  line L28 (-20.2245, -23.1429) -> (-18.5, -27)
  line L29 (-18.5, -27) -> (-20.5, -27)
loft "Loft9" add profiles "roof_pa08", "roof_pb08" section 1 section 2 separate body makes body 9
ref_plane "WorkPlane19" through (59.6, 0, 0) normal (1, 0, 0) x (0, 1, 0)
sketch "roof_pa09" plane through (59.6, 0, 0) normal (1, 0, 0) x (0, 0, -1)
  line L0 (-20.5, -27) -> (-22.2245, -23.1429)
  line L1 (-22.2245, -23.1429) -> (-23.6837, -19.2857)
  line L2 (-23.6837, -19.2857) -> (-24.8776, -15.4286)
  line L3 (-24.8776, -15.4286) -> (-25.8061, -11.5714)
  line L4 (-25.8061, -11.5714) -> (-26.4694, -7.7143)
  line L5 (-26.4694, -7.7143) -> (-26.8673, -3.8571)
  line L6 (-26.8673, -3.8571) -> (-27, 0)
  line L7 (-27, 0) -> (-26.8673, 3.8571)
  line L8 (-26.8673, 3.8571) -> (-26.4694, 7.7143)
  line L9 (-26.4694, 7.7143) -> (-25.8061, 11.5714)
  line L10 (-25.8061, 11.5714) -> (-24.8776, 15.4286)
  line L11 (-24.8776, 15.4286) -> (-23.6837, 19.2857)
  line L12 (-23.6837, 19.2857) -> (-22.2245, 23.1429)
  line L13 (-22.2245, 23.1429) -> (-20.5, 27)
  line L14 (-20.5, 27) -> (-18.5, 27)
  line L15 (-18.5, 27) -> (-20.2245, 23.1429)
  line L16 (-20.2245, 23.1429) -> (-21.6837, 19.2857)
  line L17 (-21.6837, 19.2857) -> (-22.8776, 15.4286)
  line L18 (-22.8776, 15.4286) -> (-23.8061, 11.5714)
  line L19 (-23.8061, 11.5714) -> (-24.4694, 7.7143)
  line L20 (-24.4694, 7.7143) -> (-24.8673, 3.8571)
  line L21 (-24.8673, 3.8571) -> (-25, 0)
  line L22 (-25, 0) -> (-24.8673, -3.8571)
  line L23 (-24.8673, -3.8571) -> (-24.4694, -7.7143)
  line L24 (-24.4694, -7.7143) -> (-23.8061, -11.5714)
  line L25 (-23.8061, -11.5714) -> (-22.8776, -15.4286)
  line L26 (-22.8776, -15.4286) -> (-21.6837, -19.2857)
  line L27 (-21.6837, -19.2857) -> (-20.2245, -23.1429)
  line L28 (-20.2245, -23.1429) -> (-18.5, -27)
  line L29 (-18.5, -27) -> (-20.5, -27)
ref_plane "WorkPlane20" through (90.4, 0, 0) normal (1, 0, 0) x (0, 1, 0)
sketch "roof_pb09" plane through (90.4, 0, 0) normal (1, 0, 0) x (0, 0, -1)
  line L0 (-20.5, -27) -> (-22.2245, -23.1429)
  line L1 (-22.2245, -23.1429) -> (-23.6837, -19.2857)
  line L2 (-23.6837, -19.2857) -> (-24.8776, -15.4286)
  line L3 (-24.8776, -15.4286) -> (-25.8061, -11.5714)
  line L4 (-25.8061, -11.5714) -> (-26.4694, -7.7143)
  line L5 (-26.4694, -7.7143) -> (-26.8673, -3.8571)
  line L6 (-26.8673, -3.8571) -> (-27, 0)
  line L7 (-27, 0) -> (-26.8673, 3.8571)
  line L8 (-26.8673, 3.8571) -> (-26.4694, 7.7143)
  line L9 (-26.4694, 7.7143) -> (-25.8061, 11.5714)
  line L10 (-25.8061, 11.5714) -> (-24.8776, 15.4286)
  line L11 (-24.8776, 15.4286) -> (-23.6837, 19.2857)
  line L12 (-23.6837, 19.2857) -> (-22.2245, 23.1429)
  line L13 (-22.2245, 23.1429) -> (-20.5, 27)
  line L14 (-20.5, 27) -> (-18.5, 27)
  line L15 (-18.5, 27) -> (-20.2245, 23.1429)
  line L16 (-20.2245, 23.1429) -> (-21.6837, 19.2857)
  line L17 (-21.6837, 19.2857) -> (-22.8776, 15.4286)
  line L18 (-22.8776, 15.4286) -> (-23.8061, 11.5714)
  line L19 (-23.8061, 11.5714) -> (-24.4694, 7.7143)
  line L20 (-24.4694, 7.7143) -> (-24.8673, 3.8571)
  line L21 (-24.8673, 3.8571) -> (-25, 0)
  line L22 (-25, 0) -> (-24.8673, -3.8571)
  line L23 (-24.8673, -3.8571) -> (-24.4694, -7.7143)
  line L24 (-24.4694, -7.7143) -> (-23.8061, -11.5714)
  line L25 (-23.8061, -11.5714) -> (-22.8776, -15.4286)
  line L26 (-22.8776, -15.4286) -> (-21.6837, -19.2857)
  line L27 (-21.6837, -19.2857) -> (-20.2245, -23.1429)
  line L28 (-20.2245, -23.1429) -> (-18.5, -27)
  line L29 (-18.5, -27) -> (-20.5, -27)
loft "Loft10" add profiles "roof_pa09", "roof_pb09" section 1 section 2 separate body makes body 10
ref_plane "WorkPlane21" through (89.6, 0, 0) normal (1, 0, 0) x (0, 1, 0)
sketch "roof_pa10" plane through (89.6, 0, 0) normal (1, 0, 0) x (0, 0, -1)
  line L0 (-20.5, -27) -> (-22.2245, -23.1429)
  line L1 (-22.2245, -23.1429) -> (-23.6837, -19.2857)
  line L2 (-23.6837, -19.2857) -> (-24.8776, -15.4286)
  line L3 (-24.8776, -15.4286) -> (-25.8061, -11.5714)
  line L4 (-25.8061, -11.5714) -> (-26.4694, -7.7143)
  line L5 (-26.4694, -7.7143) -> (-26.8673, -3.8571)
  line L6 (-26.8673, -3.8571) -> (-27, 0)
  line L7 (-27, 0) -> (-26.8673, 3.8571)
  line L8 (-26.8673, 3.8571) -> (-26.4694, 7.7143)
  line L9 (-26.4694, 7.7143) -> (-25.8061, 11.5714)
  line L10 (-25.8061, 11.5714) -> (-24.8776, 15.4286)
  line L11 (-24.8776, 15.4286) -> (-23.6837, 19.2857)
  line L12 (-23.6837, 19.2857) -> (-22.2245, 23.1429)
  line L13 (-22.2245, 23.1429) -> (-20.5, 27)
  line L14 (-20.5, 27) -> (-18.5, 27)
  line L15 (-18.5, 27) -> (-20.2245, 23.1429)
  line L16 (-20.2245, 23.1429) -> (-21.6837, 19.2857)
  line L17 (-21.6837, 19.2857) -> (-22.8776, 15.4286)
  line L18 (-22.8776, 15.4286) -> (-23.8061, 11.5714)
  line L19 (-23.8061, 11.5714) -> (-24.4694, 7.7143)
  line L20 (-24.4694, 7.7143) -> (-24.8673, 3.8571)
  line L21 (-24.8673, 3.8571) -> (-25, 0)
  line L22 (-25, 0) -> (-24.8673, -3.8571)
  line L23 (-24.8673, -3.8571) -> (-24.4694, -7.7143)
  line L24 (-24.4694, -7.7143) -> (-23.8061, -11.5714)
  line L25 (-23.8061, -11.5714) -> (-22.8776, -15.4286)
  line L26 (-22.8776, -15.4286) -> (-21.6837, -19.2857)
  line L27 (-21.6837, -19.2857) -> (-20.2245, -23.1429)
  line L28 (-20.2245, -23.1429) -> (-18.5, -27)
  line L29 (-18.5, -27) -> (-20.5, -27)
ref_plane "WorkPlane22" through (120.4, 0, 0) normal (1, 0, 0) x (0, 1, 0)
sketch "roof_pb10" plane through (120.4, 0, 0) normal (1, 0, 0) x (0, 0, -1)
  line L0 (-20.5, -27) -> (-22.2245, -23.1429)
  line L1 (-22.2245, -23.1429) -> (-23.6837, -19.2857)
  line L2 (-23.6837, -19.2857) -> (-24.8776, -15.4286)
  line L3 (-24.8776, -15.4286) -> (-25.8061, -11.5714)
  line L4 (-25.8061, -11.5714) -> (-26.4694, -7.7143)
  line L5 (-26.4694, -7.7143) -> (-26.8673, -3.8571)
  line L6 (-26.8673, -3.8571) -> (-27, 0)
  line L7 (-27, 0) -> (-26.8673, 3.8571)
  line L8 (-26.8673, 3.8571) -> (-26.4694, 7.7143)
  line L9 (-26.4694, 7.7143) -> (-25.8061, 11.5714)
  line L10 (-25.8061, 11.5714) -> (-24.8776, 15.4286)
  line L11 (-24.8776, 15.4286) -> (-23.6837, 19.2857)
  line L12 (-23.6837, 19.2857) -> (-22.2245, 23.1429)
  line L13 (-22.2245, 23.1429) -> (-20.5, 27)
  line L14 (-20.5, 27) -> (-18.5, 27)
  line L15 (-18.5, 27) -> (-20.2245, 23.1429)
  line L16 (-20.2245, 23.1429) -> (-21.6837, 19.2857)
  line L17 (-21.6837, 19.2857) -> (-22.8776, 15.4286)
  line L18 (-22.8776, 15.4286) -> (-23.8061, 11.5714)
  line L19 (-23.8061, 11.5714) -> (-24.4694, 7.7143)
  line L20 (-24.4694, 7.7143) -> (-24.8673, 3.8571)
  line L21 (-24.8673, 3.8571) -> (-25, 0)
  line L22 (-25, 0) -> (-24.8673, -3.8571)
  line L23 (-24.8673, -3.8571) -> (-24.4694, -7.7143)
  line L24 (-24.4694, -7.7143) -> (-23.8061, -11.5714)
  line L25 (-23.8061, -11.5714) -> (-22.8776, -15.4286)
  line L26 (-22.8776, -15.4286) -> (-21.6837, -19.2857)
  line L27 (-21.6837, -19.2857) -> (-20.2245, -23.1429)
  line L28 (-20.2245, -23.1429) -> (-18.5, -27)
  line L29 (-18.5, -27) -> (-20.5, -27)
loft "Loft11" add profiles "roof_pa10", "roof_pb10" section 1 section 2 separate body makes body 11
ref_plane "WorkPlane23" through (119.6, 0, 0) normal (1, 0, 0) x (0, 1, 0)
sketch "roof_pa11" plane through (119.6, 0, 0) normal (1, 0, 0) x (0, 0, -1)
  line L0 (-20.5, -27) -> (-22.2245, -23.1429)
  line L1 (-22.2245, -23.1429) -> (-23.6837, -19.2857)
  line L2 (-23.6837, -19.2857) -> (-24.8776, -15.4286)
  line L3 (-24.8776, -15.4286) -> (-25.8061, -11.5714)
  line L4 (-25.8061, -11.5714) -> (-26.4694, -7.7143)
  line L5 (-26.4694, -7.7143) -> (-26.8673, -3.8571)
  line L6 (-26.8673, -3.8571) -> (-27, 0)
  line L7 (-27, 0) -> (-26.8673, 3.8571)
  line L8 (-26.8673, 3.8571) -> (-26.4694, 7.7143)
  line L9 (-26.4694, 7.7143) -> (-25.8061, 11.5714)
  line L10 (-25.8061, 11.5714) -> (-24.8776, 15.4286)
  line L11 (-24.8776, 15.4286) -> (-23.6837, 19.2857)
  line L12 (-23.6837, 19.2857) -> (-22.2245, 23.1429)
  line L13 (-22.2245, 23.1429) -> (-20.5, 27)
  line L14 (-20.5, 27) -> (-18.5, 27)
  line L15 (-18.5, 27) -> (-20.2245, 23.1429)
  line L16 (-20.2245, 23.1429) -> (-21.6837, 19.2857)
  line L17 (-21.6837, 19.2857) -> (-22.8776, 15.4286)
  line L18 (-22.8776, 15.4286) -> (-23.8061, 11.5714)
  line L19 (-23.8061, 11.5714) -> (-24.4694, 7.7143)
  line L20 (-24.4694, 7.7143) -> (-24.8673, 3.8571)
  line L21 (-24.8673, 3.8571) -> (-25, 0)
  line L22 (-25, 0) -> (-24.8673, -3.8571)
  line L23 (-24.8673, -3.8571) -> (-24.4694, -7.7143)
  line L24 (-24.4694, -7.7143) -> (-23.8061, -11.5714)
  line L25 (-23.8061, -11.5714) -> (-22.8776, -15.4286)
  line L26 (-22.8776, -15.4286) -> (-21.6837, -19.2857)
  line L27 (-21.6837, -19.2857) -> (-20.2245, -23.1429)
  line L28 (-20.2245, -23.1429) -> (-18.5, -27)
  line L29 (-18.5, -27) -> (-20.5, -27)
ref_plane "WorkPlane24" through (124.6857, 0, 0) normal (1, 0, 0) x (0, 1, 0)
sketch "roof_pb11" plane through (124.6857, 0, 0) normal (1, 0, 0) x (0, 0, -1)
  line L0 (-18.3003, -24.3221) -> (-19.8472, -20.8475)
  line L1 (-19.8472, -20.8475) -> (-21.1561, -17.3729)
  line L2 (-21.1561, -17.3729) -> (-22.227, -13.8983)
  line L3 (-22.227, -13.8983) -> (-23.0599, -10.4238)
  line L4 (-23.0599, -10.4238) -> (-23.6549, -6.9492)
  line L5 (-23.6549, -6.9492) -> (-24.0118, -3.4746)
  line L6 (-24.0118, -3.4746) -> (-24.1308, 0)
  line L7 (-24.1308, 0) -> (-24.0118, 3.4746)
  line L8 (-24.0118, 3.4746) -> (-23.6549, 6.9492)
  line L9 (-23.6549, 6.9492) -> (-23.0599, 10.4238)
  line L10 (-23.0599, 10.4238) -> (-22.227, 13.8983)
  line L11 (-22.227, 13.8983) -> (-21.1561, 17.3729)
  line L12 (-21.1561, 17.3729) -> (-19.8472, 20.8475)
  line L13 (-19.8472, 20.8475) -> (-18.3003, 24.3221)
  line L14 (-18.3003, 24.3221) -> (-16.3003, 24.3221)
  line L15 (-16.3003, 24.3221) -> (-17.8472, 20.8475)
  line L16 (-17.8472, 20.8475) -> (-19.1561, 17.3729)
  line L17 (-19.1561, 17.3729) -> (-20.227, 13.8983)
  line L18 (-20.227, 13.8983) -> (-21.0599, 10.4238)
  line L19 (-21.0599, 10.4238) -> (-21.6549, 6.9492)
  line L20 (-21.6549, 6.9492) -> (-22.0118, 3.4746)
  line L21 (-22.0118, 3.4746) -> (-22.1308, 0)
  line L22 (-22.1308, 0) -> (-22.0118, -3.4746)
  line L23 (-22.0118, -3.4746) -> (-21.6549, -6.9492)
  line L24 (-21.6549, -6.9492) -> (-21.0599, -10.4238)
  line L25 (-21.0599, -10.4238) -> (-20.227, -13.8983)
  line L26 (-20.227, -13.8983) -> (-19.1561, -17.3729)
  line L27 (-19.1561, -17.3729) -> (-17.8472, -20.8475)
  line L28 (-17.8472, -20.8475) -> (-16.3003, -24.3221)
  line L29 (-16.3003, -24.3221) -> (-18.3003, -24.3221)
loft "Loft12" add profiles "roof_pa11", "roof_pb11" section 1 section 2 separate body makes body 12
ref_plane "WorkPlane25" through (123.8857, 0, 0) normal (1, 0, 0) x (0, 1, 0)
sketch "roof_pa12" plane through (123.8857, 0, 0) normal (1, 0, 0) x (0, 0, -1)
  line L0 (-18.3003, -24.3221) -> (-19.8472, -20.8475)
  line L1 (-19.8472, -20.8475) -> (-21.1561, -17.3729)
  line L2 (-21.1561, -17.3729) -> (-22.227, -13.8983)
  line L3 (-22.227, -13.8983) -> (-23.0599, -10.4238)
  line L4 (-23.0599, -10.4238) -> (-23.6549, -6.9492)
  line L5 (-23.6549, -6.9492) -> (-24.0118, -3.4746)
  line L6 (-24.0118, -3.4746) -> (-24.1308, 0)
  line L7 (-24.1308, 0) -> (-24.0118, 3.4746)
  line L8 (-24.0118, 3.4746) -> (-23.6549, 6.9492)
  line L9 (-23.6549, 6.9492) -> (-23.0599, 10.4238)
  line L10 (-23.0599, 10.4238) -> (-22.227, 13.8983)
  line L11 (-22.227, 13.8983) -> (-21.1561, 17.3729)
  line L12 (-21.1561, 17.3729) -> (-19.8472, 20.8475)
  line L13 (-19.8472, 20.8475) -> (-18.3003, 24.3221)
  line L14 (-18.3003, 24.3221) -> (-16.3003, 24.3221)
  line L15 (-16.3003, 24.3221) -> (-17.8472, 20.8475)
  line L16 (-17.8472, 20.8475) -> (-19.1561, 17.3729)
  line L17 (-19.1561, 17.3729) -> (-20.227, 13.8983)
  line L18 (-20.227, 13.8983) -> (-21.0599, 10.4238)
  line L19 (-21.0599, 10.4238) -> (-21.6549, 6.9492)
  line L20 (-21.6549, 6.9492) -> (-22.0118, 3.4746)
  line L21 (-22.0118, 3.4746) -> (-22.1308, 0)
  line L22 (-22.1308, 0) -> (-22.0118, -3.4746)
  line L23 (-22.0118, -3.4746) -> (-21.6549, -6.9492)
  line L24 (-21.6549, -6.9492) -> (-21.0599, -10.4238)
  line L25 (-21.0599, -10.4238) -> (-20.227, -13.8983)
  line L26 (-20.227, -13.8983) -> (-19.1561, -17.3729)
  line L27 (-19.1561, -17.3729) -> (-17.8472, -20.8475)
  line L28 (-17.8472, -20.8475) -> (-16.3003, -24.3221)
  line L29 (-16.3003, -24.3221) -> (-18.3003, -24.3221)
ref_plane "WorkPlane26" through (128.9714, 0, 0) normal (1, 0, 0) x (0, 1, 0)
sketch "roof_pb12" plane through (128.9714, 0, 0) normal (1, 0, 0) x (0, 0, -1)
  line L0 (-16.535, -22.1731) -> (-17.9394, -19.0055)
  line L1 (-17.9394, -19.0055) -> (-19.1277, -15.8379)
  line L2 (-19.1277, -15.8379) -> (-20.0999, -12.6703)
  line L3 (-20.0999, -12.6703) -> (-20.8561, -9.5027)
  line L4 (-20.8561, -9.5027) -> (-21.3962, -6.3352)
  line L5 (-21.3962, -6.3352) -> (-21.7203, -3.1676)
  line L6 (-21.7203, -3.1676) -> (-21.8283, 0)
  line L7 (-21.8283, 0) -> (-21.7203, 3.1676)
  line L8 (-21.7203, 3.1676) -> (-21.3962, 6.3352)
  line L9 (-21.3962, 6.3352) -> (-20.8561, 9.5027)
  line L10 (-20.8561, 9.5027) -> (-20.0999, 12.6703)
  line L11 (-20.0999, 12.6703) -> (-19.1277, 15.8379)
  line L12 (-19.1277, 15.8379) -> (-17.9394, 19.0055)
  line L13 (-17.9394, 19.0055) -> (-16.535, 22.1731)
  line L14 (-16.535, 22.1731) -> (-14.535, 22.1731)
  line L15 (-14.535, 22.1731) -> (-15.9394, 19.0055)
  line L16 (-15.9394, 19.0055) -> (-17.1277, 15.8379)
  line L17 (-17.1277, 15.8379) -> (-18.0999, 12.6703)
  line L18 (-18.0999, 12.6703) -> (-18.8561, 9.5027)
  line L19 (-18.8561, 9.5027) -> (-19.3962, 6.3352)
  line L20 (-19.3962, 6.3352) -> (-19.7203, 3.1676)
  line L21 (-19.7203, 3.1676) -> (-19.8283, 0)
  line L22 (-19.8283, 0) -> (-19.7203, -3.1676)
  line L23 (-19.7203, -3.1676) -> (-19.3962, -6.3352)
  line L24 (-19.3962, -6.3352) -> (-18.8561, -9.5027)
  line L25 (-18.8561, -9.5027) -> (-18.0999, -12.6703)
  line L26 (-18.0999, -12.6703) -> (-17.1277, -15.8379)
  line L27 (-17.1277, -15.8379) -> (-15.9394, -19.0055)
  line L28 (-15.9394, -19.0055) -> (-14.535, -22.1731)
  line L29 (-14.535, -22.1731) -> (-16.535, -22.1731)
loft "Loft13" add profiles "roof_pa12", "roof_pb12" section 1 section 2 separate body makes body 13
ref_plane "WorkPlane27" through (128.1714, 0, 0) normal (1, 0, 0) x (0, 1, 0)
sketch "roof_pa13" plane through (128.1714, 0, 0) normal (1, 0, 0) x (0, 0, -1)
  line L0 (-16.535, -22.1731) -> (-17.9394, -19.0055)
  line L1 (-17.9394, -19.0055) -> (-19.1277, -15.8379)
  line L2 (-19.1277, -15.8379) -> (-20.0999, -12.6703)
  line L3 (-20.0999, -12.6703) -> (-20.8561, -9.5027)
  line L4 (-20.8561, -9.5027) -> (-21.3962, -6.3352)
  line L5 (-21.3962, -6.3352) -> (-21.7203, -3.1676)
  line L6 (-21.7203, -3.1676) -> (-21.8283, 0)
  line L7 (-21.8283, 0) -> (-21.7203, 3.1676)
  line L8 (-21.7203, 3.1676) -> (-21.3962, 6.3352)
  line L9 (-21.3962, 6.3352) -> (-20.8561, 9.5027)
  line L10 (-20.8561, 9.5027) -> (-20.0999, 12.6703)
  line L11 (-20.0999, 12.6703) -> (-19.1277, 15.8379)
  line L12 (-19.1277, 15.8379) -> (-17.9394, 19.0055)
  line L13 (-17.9394, 19.0055) -> (-16.535, 22.1731)
  line L14 (-16.535, 22.1731) -> (-14.535, 22.1731)
  line L15 (-14.535, 22.1731) -> (-15.9394, 19.0055)
  line L16 (-15.9394, 19.0055) -> (-17.1277, 15.8379)
  line L17 (-17.1277, 15.8379) -> (-18.0999, 12.6703)
  line L18 (-18.0999, 12.6703) -> (-18.8561, 9.5027)
  line L19 (-18.8561, 9.5027) -> (-19.3962, 6.3352)
  line L20 (-19.3962, 6.3352) -> (-19.7203, 3.1676)
  line L21 (-19.7203, 3.1676) -> (-19.8283, 0)
  line L22 (-19.8283, 0) -> (-19.7203, -3.1676)
  line L23 (-19.7203, -3.1676) -> (-19.3962, -6.3352)
  line L24 (-19.3962, -6.3352) -> (-18.8561, -9.5027)
  line L25 (-18.8561, -9.5027) -> (-18.0999, -12.6703)
  line L26 (-18.0999, -12.6703) -> (-17.1277, -15.8379)
  line L27 (-17.1277, -15.8379) -> (-15.9394, -19.0055)
  line L28 (-15.9394, -19.0055) -> (-14.535, -22.1731)
  line L29 (-14.535, -22.1731) -> (-16.535, -22.1731)
ref_plane "WorkPlane28" through (133.2571, 0, 0) normal (1, 0, 0) x (0, 1, 0)
sketch "roof_pb13" plane through (133.2571, 0, 0) normal (1, 0, 0) x (0, 0, -1)
  line L0 (-14.9035, -20.1869) -> (-16.1761, -17.303)
  line L1 (-16.1761, -17.303) -> (-17.2529, -14.4192)
  line L2 (-17.2529, -14.4192) -> (-18.1339, -11.5353)
  line L3 (-18.1339, -11.5353) -> (-18.8192, -8.6515)
  line L4 (-18.8192, -8.6515) -> (-19.3086, -5.7677)
  line L5 (-19.3086, -5.7677) -> (-19.6023, -2.8838)
  line L6 (-19.6023, -2.8838) -> (-19.7002, 0)
  line L7 (-19.7002, 0) -> (-19.6023, 2.8838)
  line L8 (-19.6023, 2.8838) -> (-19.3086, 5.7677)
  line L9 (-19.3086, 5.7677) -> (-18.8192, 8.6515)
  line L10 (-18.8192, 8.6515) -> (-18.1339, 11.5353)
  line L11 (-18.1339, 11.5353) -> (-17.2529, 14.4192)
  line L12 (-17.2529, 14.4192) -> (-16.1761, 17.303)
  line L13 (-16.1761, 17.303) -> (-14.9035, 20.1869)
  line L14 (-14.9035, 20.1869) -> (-12.9035, 20.1869)
  line L15 (-12.9035, 20.1869) -> (-14.1761, 17.303)
  line L16 (-14.1761, 17.303) -> (-15.2529, 14.4192)
  line L17 (-15.2529, 14.4192) -> (-16.1339, 11.5353)
  line L18 (-16.1339, 11.5353) -> (-16.8192, 8.6515)
  line L19 (-16.8192, 8.6515) -> (-17.3086, 5.7677)
  line L20 (-17.3086, 5.7677) -> (-17.6023, 2.8838)
  line L21 (-17.6023, 2.8838) -> (-17.7002, 0)
  line L22 (-17.7002, 0) -> (-17.6023, -2.8838)
  line L23 (-17.6023, -2.8838) -> (-17.3086, -5.7677)
  line L24 (-17.3086, -5.7677) -> (-16.8192, -8.6515)
  line L25 (-16.8192, -8.6515) -> (-16.1339, -11.5353)
  line L26 (-16.1339, -11.5353) -> (-15.2529, -14.4192)
  line L27 (-15.2529, -14.4192) -> (-14.1761, -17.303)
  line L28 (-14.1761, -17.303) -> (-12.9035, -20.1869)
  line L29 (-12.9035, -20.1869) -> (-14.9035, -20.1869)
loft "Loft14" add profiles "roof_pa13", "roof_pb13" section 1 section 2 separate body makes body 14
ref_plane "WorkPlane29" through (132.4571, 0, 0) normal (1, 0, 0) x (0, 1, 0)